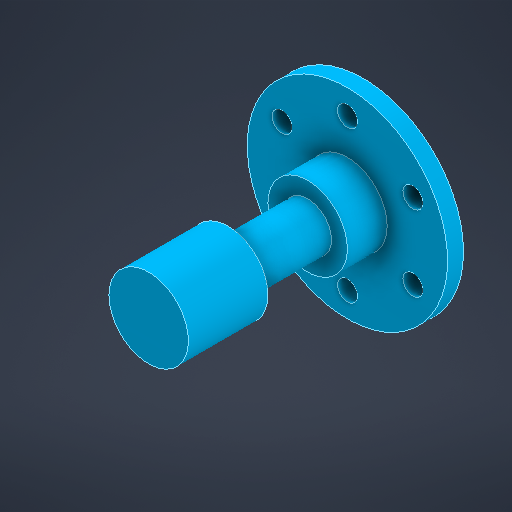
# Autodesk Inventor part: carretel
Saved by Autodesk Inventor 2026 (Build 300175000, 175)
## iProperties
Created: 2025-04-24
Part Number: carretel
Material: Genérico
Document SubType Name: Modeling
Designer: MARIA
Mass: 2.39945 g
Surface Area: 19.5146 cm^2
Volume: 2.39945 cm^3
Density: 1 g/cm^3
Appearance: Padrão
Author: MARIA
Autodesk Inventor part; units mm, degrees
ref_plane "YZ Plane" through (0, 0, 0) normal (1, 0, 0) x (0, 1, 0)
ref_plane "XZ Plane" through (0, 0, 0) normal (0, 1, 0) x (-1, 0, 0)
ref_plane "XY Plane" through (0, 0, 0) normal (0, 0, 1) x (1, 0, 0)
sketch "Esboço1" plane through (0, 0, 0) normal (0, 0, 1) x (1, 0, 0)
  circle A0 centre (0, 0) radius 12.6
  dimension "d0" = 25.2
  constraints: 1 centre point, 1 coincident
  measures "d0" diameter of A0
extrude "Extrusão1" add sketch "Esboço1" along normal blind 2
sketch "Esboço2" plane through (0, 0, 2) normal (0, 0, 1) x (1, 0, 0)
  circle A0 centre (0, 0) radius 5
  circle A1 centre (0, 9.5) radius 1.25
  dimension "d3" = 10
  dimension "d4" = 2.5
  dimension "d5" = 9.5
  dimension "d6" = 0
  constraints: 2 centre point, 1 coincident
  measures "d3" diameter of A0
  measures "d4" diameter of A1
  measures "d5" distance of A0.centre A1.centre
  measures "d6" horizontal distance of A0.centre A1.centre
extrude "Extrusão2" add sketch "Esboço2" along normal blind 5 contours A0
sketch "Esboço3" plane through (0, 0, 2) normal (0, 0, 1) x (1, 0, 0)
  circle A0 centre (0, 9.5) radius 1.25
  circle A1 centre (0, 0) radius 5 projected
  dimension "d9" = 2.5
  dimension "d10" = 9.5
  dimension "d11" = 0
  constraints: 1 centre point
  measures "d9" diameter of A0
  measures "d10" distance of A1.centre A0.centre
  measures "d11" horizontal distance of A1.centre A0.centre
extrude "Extrusão3" cut sketch "Esboço3" against normal through all contours A0
pattern_circular "Padrão circular1" count 6 over 360 about axis through (0, 0, 0) along (0, 0, 1) of "Extrusão3"
sketch "Esboço4" plane through (0, 0, 7) normal (0, 0, 1) x (1, 0, 0)
  circle A0 centre (0, 0) radius 3
  dimension "d17" = 6
  constraints: 1 centre point, 1 coincident
  measures "d17" diameter of A0
extrude "Extrusão4" add sketch "Esboço4" along normal blind 10
sketch "Esboço5" plane through (0, 0, 17) normal (0, 0, 1) x (1, 0, 0)
  circle A0 centre (0, 0) radius 5
  dimension "d20" = 10
  constraints: 1 centre point, 1 coincident
  measures "d20" diameter of A0
extrude "Extrusão5" add sketch "Esboço5" along normal blind 10
